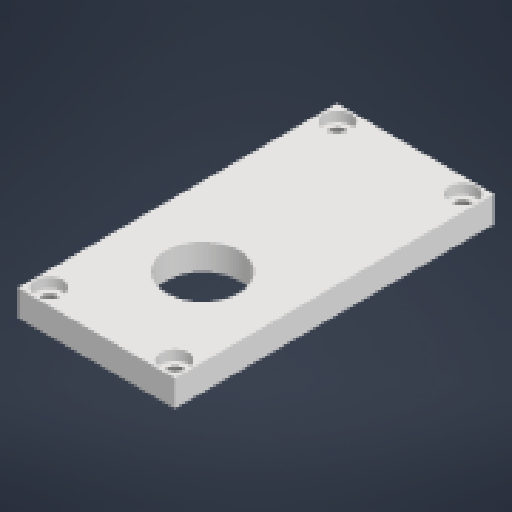
# Autodesk Inventor part: nắp
Saved by Autodesk Inventor 2026.2 (Build 302298000, 298)
## iProperties
Created: 2026-03-17
Part Number: nắp
Material: Generic
Document SubType Name: Modeling
Designer: thita
Density: 1 g/cm^3
Appearance: Default
Author: thita
Autodesk Inventor part; units mm, degrees
ref_plane "YZ Plane" through (0, 0, 0) normal (1, 0, 0) x (0, 1, 0)
ref_plane "XZ Plane" through (0, 0, 0) normal (0, 1, 0) x (-1, 0, 0)
sketch "Sketch1" plane through (0, 0, 0) normal (0, 1, 0) x (-1, 0, 0)
  line L0 (10.3, -25.8) -> (10.3, 25.8)
  line L1 (10.3, 25.8) -> (-10.3, 25.8)
  line L2 (-10.3, 25.8) -> (-10.3, -25.8)
  line L3 (-10.3, -25.8) -> (10.3, -25.8)
  line L4 (10.3, -25.8) -> (-10.3, 25.8) construction
  line L5 (10.3, 25.8) -> (-10.3, -25.8) construction
  line L6 (15, -30.5) -> (-14.9994, -30.5003)
  line L7 (-14.9994, -30.5003) -> (-15, 30.5)
  line L8 (-15, 30.5) -> (14.9994, 30.5003)
  line L9 (14.9994, 30.5003) -> (15, -30.5)
  line L10 (15, -30.5) -> (-15, 30.5) construction
  line L11 (-14.9994, -30.5003) -> (14.9994, 30.5003) construction
  line L12 (14.9994, 30.5003) -> (14.9995, 27.5003)
  line L13 (14.9995, 27.5003) -> (11.9995, 27.5002)
  circle A0 centre (11.9995, 27.5002) radius 1.5
  line L14 (14.9997, 0.0001) -> (12.9995, 0.0001)
  line L15 (0.0003, -30.5001) -> (0.0003, -27.8009)
  circle A1 centre (11.9995, -27.5) radius 1.5
  circle A2 centre (-11.9989, 27.5002) radius 1.5
  circle A3 centre (-11.9989, -27.5) radius 1.5
  point P0 (0, 0)
  point P1 (0, 0)
  dimension "d0" = 3
  dimension "d1" = 3
  dimension "d2" = 3
  constraints: 32 end point, 6 midpoint, 4 centre point, 4 parallel, 3 perpendicular, 3 symmetric about line, 1 coincident, 1 horizontal, 1 point on line, 1 vertical, 3 other
  measures "d0" distance of L8.end L12.end
  measures "d1" distance of L12.end L13.end
  measures "d2" diameter of A0
extrude "Extrusion1" add sketch "Sketch1" along normal blind 5 contours L3 L2 L1 L0 | L6 L7 L8 L9
sketch "Sketch2" plane through (0, 5, 0) normal (0, 1, 0) x (1, 0, 0)
  circle A0 centre (-11.9995, -27.5002) radius 1.5 projected
  circle A1 centre (-11.9995, -27.5002) radius 2.6
  circle A2 centre (11.9989, -27.5002) radius 1.5 projected
  circle A3 centre (11.9989, -27.5002) radius 2.6
  circle A4 centre (-11.9995, 27.5) radius 1.5 projected
  circle A5 centre (-11.9995, 27.5) radius 2.6
  circle A6 centre (11.9989, 27.5) radius 1.5 projected
  circle A7 centre (11.9989, 27.5) radius 2.6
  point P0 (0, 0)
  dimension "d5" = 5.2
  dimension "d6" = 5.2
  dimension "d7" = 5.2
  dimension "d8" = 5.2
  constraints: 4 centre point, 4 coincident
  measures "d5" diameter of A1
  measures "d6" diameter of A3
  measures "d7" diameter of A5
  measures "d8" diameter of A7
extrude "Extrusion2" cut sketch "Sketch2" against normal blind 2
thread "Thread1" size "M3x0.5" class "6H" standard "ISO Metric profile" length 12
thread "Thread2" size "M3x0.5" class "6H" standard "ISO Metric profile" length 12
thread "Thread3" size "M3x0.5" class "6H" standard "ISO Metric profile" length 12
thread "Thread4" size "M3x0.5" class "6H" standard "ISO Metric profile" length 12
ref_plane "Work Plane1" through (-23.1777, 0, -34.5208) normal (0, 1, 0) x (0, 0, 1)
sketch "Sketch3" plane through (0, 5, 0) normal (0, 1, 0) x (1, 0, 0)
  line L0 (1.9772, -9.9005) -> (1.8848, -9.962) projected
  arc A0 (1.9772, -9.9005) -> (1.973, -9.874) centre (-0.0002, -10.2001) ccw projected
  line L1 (1.8662, -9.8441) -> (1.973, -9.874) projected
  line L2 (1.9545, -9.777) -> (1.8662, -9.8441) projected
  arc A1 (1.9545, -9.777) -> (1.9487, -9.7507) centre (-0.0002, -10.2001) ccw projected
  line L3 (1.8401, -9.7276) -> (1.9487, -9.7507) projected
  line L4 (1.9241, -9.6551) -> (1.8401, -9.7276) projected
  arc A2 (1.9241, -9.6551) -> (1.9166, -9.6292) centre (-0.0002, -10.2001) ccw projected
  line L5 (1.8068, -9.613) -> (1.9166, -9.6292) projected
  line L6 (1.8861, -9.5353) -> (1.8068, -9.613) projected
  arc A3 (1.8861, -9.5353) -> (1.877, -9.51) centre (-0.0002, -10.2001) ccw projected
  line L7 (1.7664, -9.5007) -> (1.877, -9.51) projected
  line L8 (1.8406, -9.4182) -> (1.7664, -9.5007) projected
  arc A4 (1.8406, -9.4182) -> (1.8299, -9.3935) centre (-0.0002, -10.2001) ccw projected
  line L9 (1.719, -9.3911) -> (1.8299, -9.3935) projected
  line L10 (1.7879, -9.3041) -> (1.719, -9.3911) projected
  arc A5 (1.7879, -9.3041) -> (1.7757, -9.2802) centre (-0.0002, -10.2001) ccw projected
  line L11 (1.6648, -9.2848) -> (1.7757, -9.2802) projected
  line L12 (1.7281, -9.1936) -> (1.6648, -9.2848) projected
  arc A6 (1.7281, -9.1936) -> (1.7144, -9.1705) centre (-0.0002, -10.2001) ccw projected
  line L13 (1.604, -9.1821) -> (1.7144, -9.1705) projected
  line L14 (1.6615, -9.0871) -> (1.604, -9.1821) projected
  arc A7 (1.6615, -9.0871) -> (1.6464, -9.0649) centre (-0.0002, -10.2001) ccw projected
  line L15 (1.5369, -9.0833) -> (1.6464, -9.0649) projected
  line L16 (1.5883, -8.985) -> (1.5369, -9.0833) projected
  arc A8 (1.5883, -8.985) -> (1.5718, -8.9637) centre (-0.0002, -10.2001) ccw projected
  line L17 (1.4638, -8.989) -> (1.5718, -8.9637) projected
  line L18 (1.5089, -8.8876) -> (1.4638, -8.989) projected
  arc A9 (1.5089, -8.8876) -> (1.4911, -8.8674) centre (-0.0002, -10.2001) ccw projected
  line L19 (1.3848, -8.8995) -> (1.4911, -8.8674) projected
  line L20 (1.4235, -8.7954) -> (1.3848, -8.8995) projected
  arc A10 (1.4235, -8.7954) -> (1.4045, -8.7764) centre (-0.0002, -10.2001) ccw projected
  line L21 (1.3004, -8.8151) -> (1.4045, -8.7764) projected
  line L22 (1.3325, -8.7088) -> (1.3004, -8.8151) projected
  arc A11 (1.3325, -8.7088) -> (1.3123, -8.6911) centre (-0.0002, -10.2001) ccw projected
  line L23 (1.2109, -8.7362) -> (1.3123, -8.6911) projected
  line L24 (1.2362, -8.6281) -> (1.2109, -8.7362) projected
  arc A12 (1.2362, -8.6281) -> (1.215, -8.6116) centre (-0.0002, -10.2001) ccw projected
  line L25 (1.1166, -8.663) -> (1.215, -8.6116) projected
  line L26 (1.1351, -8.5536) -> (1.1166, -8.663) projected
  arc A13 (1.1351, -8.5536) -> (1.1128, -8.5384) centre (-0.0002, -10.2001) ccw projected
  line L27 (1.0179, -8.5959) -> (1.1128, -8.5384) projected
  line L28 (1.0294, -8.4855) -> (1.0179, -8.5959) projected
  arc A14 (1.0294, -8.4855) -> (1.0063, -8.4718) centre (-0.0002, -10.2001) ccw projected
  line L29 (0.9151, -8.5351) -> (1.0063, -8.4718) projected
  line L30 (0.9197, -8.4243) -> (0.9151, -8.5351) projected
  arc A15 (0.9197, -8.4243) -> (0.8958, -8.4121) centre (-0.0002, -10.2001) ccw projected
  line L31 (0.8088, -8.481) -> (0.8958, -8.4121) projected
  line L32 (0.8064, -8.37) -> (0.8088, -8.481) projected
  arc A16 (0.8064, -8.37) -> (0.7817, -8.3593) centre (-0.0002, -10.2001) ccw projected
  line L33 (0.6992, -8.4336) -> (0.7817, -8.3593) projected
  line L34 (0.6899, -8.323) -> (0.6992, -8.4336) projected
  arc A17 (0.6899, -8.323) -> (0.6646, -8.3139) centre (-0.0002, -10.2001) ccw projected
  line L35 (0.5869, -8.3931) -> (0.6646, -8.3139) projected
  line L36 (0.5707, -8.2833) -> (0.5869, -8.3931) projected
  arc A18 (0.5707, -8.2833) -> (0.5449, -8.2758) centre (-0.0002, -10.2001) ccw projected
  line L37 (0.4723, -8.3598) -> (0.5449, -8.2758) projected
  line L38 (0.4492, -8.2513) -> (0.4723, -8.3598) projected
  arc A19 (0.4492, -8.2513) -> (0.423, -8.2454) centre (-0.0002, -10.2001) ccw projected
  line L39 (0.3558, -8.3338) -> (0.423, -8.2454) projected
  line L40 (0.3259, -8.2269) -> (0.3558, -8.3338) projected
  arc A20 (0.3259, -8.2269) -> (0.2994, -8.2227) centre (-0.0002, -10.2001) ccw projected
  line L41 (0.2379, -8.3151) -> (0.2994, -8.2227) projected
  line L42 (0.2014, -8.2103) -> (0.2379, -8.3151) projected
  arc A21 (0.2014, -8.2103) -> (0.1746, -8.2078) centre (-0.0002, -10.2001) ccw projected
  line L43 (0.1191, -8.3039) -> (0.1746, -8.2078) projected
  line L44 (0.076, -8.2016) -> (0.1191, -8.3039) projected
  arc A22 (0.076, -8.2016) -> (0.0492, -8.2007) centre (-0.0002, -10.2001) ccw projected
  line L45 (-0.0002, -8.3001) -> (0.0492, -8.2007) projected
  line L46 (-0.0496, -8.2007) -> (-0.0002, -8.3001) projected
  arc A23 (-0.0496, -8.2007) -> (-0.0765, -8.2016) centre (-0.0002, -10.2001) ccw projected
  line L47 (-0.1195, -8.3039) -> (-0.0765, -8.2016) projected
  line L48 (-0.175, -8.2078) -> (-0.1195, -8.3039) projected
  arc A24 (-0.175, -8.2078) -> (-0.2018, -8.2103) centre (-0.0002, -10.2001) ccw projected
  line L49 (-0.2383, -8.3151) -> (-0.2018, -8.2103) projected
  line L50 (-0.2998, -8.2227) -> (-0.2383, -8.3151) projected
  arc A25 (-0.2998, -8.2227) -> (-0.3263, -8.2269) centre (-0.0002, -10.2001) ccw projected
  line L51 (-0.3562, -8.3338) -> (-0.3263, -8.2269) projected
  line L52 (-0.4234, -8.2454) -> (-0.3562, -8.3338) projected
  arc A26 (-0.4234, -8.2454) -> (-0.4496, -8.2513) centre (-0.0002, -10.2001) ccw projected
  line L53 (-0.4727, -8.3598) -> (-0.4496, -8.2513) projected
  line L54 (-0.5453, -8.2758) -> (-0.4727, -8.3598) projected
  arc A27 (-0.5453, -8.2758) -> (-0.5711, -8.2833) centre (-0.0002, -10.2001) ccw projected
  line L55 (-0.5873, -8.3931) -> (-0.5711, -8.2833) projected
  line L56 (-0.665, -8.3139) -> (-0.5873, -8.3931) projected
  arc A28 (-0.665, -8.3139) -> (-0.6903, -8.323) centre (-0.0002, -10.2001) ccw projected
  line L57 (-0.6996, -8.4336) -> (-0.6903, -8.323) projected
  line L58 (-0.7821, -8.3593) -> (-0.6996, -8.4336) projected
  arc A29 (-0.7821, -8.3593) -> (-0.8068, -8.37) centre (-0.0002, -10.2001) ccw projected
  line L59 (-0.8092, -8.481) -> (-0.8068, -8.37) projected
  line L60 (-0.8962, -8.4121) -> (-0.8092, -8.481) projected
  arc A30 (-0.8962, -8.4121) -> (-0.9201, -8.4243) centre (-0.0002, -10.2001) ccw projected
  line L61 (-0.9155, -8.5352) -> (-0.9201, -8.4243) projected
  line L62 (-1.0067, -8.4719) -> (-0.9155, -8.5352) projected
  arc A31 (-1.0067, -8.4719) -> (-1.0298, -8.4855) centre (-0.0002, -10.2001) ccw projected
  line L63 (-1.0183, -8.5959) -> (-1.0298, -8.4855) projected
  line L64 (-1.1132, -8.5385) -> (-1.0183, -8.5959) projected
  arc A32 (-1.1132, -8.5385) -> (-1.1355, -8.5536) centre (-0.0002, -10.2001) ccw projected
  line L65 (-1.117, -8.663) -> (-1.1355, -8.5536) projected
  line L66 (-1.2154, -8.6116) -> (-1.117, -8.663) projected
  arc A33 (-1.2154, -8.6116) -> (-1.2366, -8.6281) centre (-0.0002, -10.2001) ccw projected
  line L67 (-1.2113, -8.7362) -> (-1.2366, -8.6281) projected
  line L68 (-1.3127, -8.6911) -> (-1.2113, -8.7362) projected
  arc A34 (-1.3127, -8.6911) -> (-1.3329, -8.7088) centre (-0.0002, -10.2001) ccw projected
  line L69 (-1.3008, -8.8151) -> (-1.3329, -8.7088) projected
  line L70 (-1.4049, -8.7765) -> (-1.3008, -8.8151) projected
  arc A35 (-1.4049, -8.7765) -> (-1.4239, -8.7955) centre (-0.0002, -10.2001) ccw projected
  line L71 (-1.3852, -8.8995) -> (-1.4239, -8.7955) projected
  line L72 (-1.4915, -8.8675) -> (-1.3852, -8.8995) projected
  arc A36 (-1.4915, -8.8675) -> (-1.5093, -8.8876) centre (-0.0002, -10.2001) ccw projected
  line L73 (-1.4642, -8.989) -> (-1.5093, -8.8876) projected
  line L74 (-1.5722, -8.9637) -> (-1.4642, -8.989) projected
  arc A37 (-1.5722, -8.9637) -> (-1.5887, -8.985) centre (-0.0002, -10.2001) ccw projected
  line L75 (-1.5373, -9.0834) -> (-1.5887, -8.985) projected
  line L76 (-1.6468, -9.0649) -> (-1.5373, -9.0834) projected
  arc A38 (-1.6468, -9.0649) -> (-1.6619, -9.0871) centre (-0.0002, -10.2001) ccw projected
  line L77 (-1.6044, -9.1821) -> (-1.6619, -9.0871) projected
  line L78 (-1.7148, -9.1705) -> (-1.6044, -9.1821) projected
  arc A39 (-1.7148, -9.1705) -> (-1.7285, -9.1937) centre (-0.0002, -10.2001) ccw projected
  line L79 (-1.6652, -9.2848) -> (-1.7285, -9.1937) projected
  line L80 (-1.7761, -9.2802) -> (-1.6652, -9.2848) projected
  arc A40 (-1.7761, -9.2802) -> (-1.7883, -9.3042) centre (-0.0002, -10.2001) ccw projected
  line L81 (-1.7194, -9.3912) -> (-1.7883, -9.3042) projected
  line L82 (-1.8303, -9.3935) -> (-1.7194, -9.3912) projected
  arc A41 (-1.8303, -9.3935) -> (-1.841, -9.4182) centre (-0.0002, -10.2001) ccw projected
  line L83 (-1.7668, -9.5007) -> (-1.841, -9.4182) projected
  line L84 (-1.8774, -9.5101) -> (-1.7668, -9.5007) projected
  arc A42 (-1.8774, -9.5101) -> (-1.8865, -9.5353) centre (-0.0002, -10.2001) ccw projected
  line L85 (-1.8072, -9.613) -> (-1.8865, -9.5353) projected
  line L86 (-1.917, -9.6293) -> (-1.8072, -9.613) projected
  arc A43 (-1.917, -9.6293) -> (-1.9245, -9.6551) centre (-0.0002, -10.2001) ccw projected
  line L87 (-1.8405, -9.7276) -> (-1.9245, -9.6551) projected
  line L88 (-1.949, -9.7508) -> (-1.8405, -9.7276) projected
  arc A44 (-1.949, -9.7508) -> (-1.9549, -9.777) centre (-0.0002, -10.2001) ccw projected
  line L89 (-1.8665, -9.8441) -> (-1.9549, -9.777) projected
  line L90 (-1.9734, -9.874) -> (-1.8665, -9.8441) projected
  arc A45 (-1.9734, -9.874) -> (-1.9776, -9.9006) centre (-0.0002, -10.2001) ccw projected
  line L91 (-1.8852, -9.962) -> (-1.9776, -9.9006) projected
  line L92 (-1.99, -9.9986) -> (-1.8852, -9.962) projected
  arc A46 (-1.99, -9.9986) -> (-1.9925, -10.0253) centre (-0.0002, -10.2001) ccw projected
  line L93 (-1.8964, -10.0809) -> (-1.9925, -10.0253) projected
  line L94 (-1.9987, -10.1239) -> (-1.8964, -10.0809) projected
  arc A47 (-1.9987, -10.1239) -> (-1.9996, -10.1508) centre (-0.0002, -10.2001) ccw projected
  line L95 (-1.9002, -10.2002) -> (-1.9996, -10.1508) projected
  line L96 (-1.9996, -10.2495) -> (-1.9002, -10.2002) projected
  arc A48 (-1.9996, -10.2495) -> (-1.9987, -10.2764) centre (-0.0002, -10.2001) ccw projected
  line L97 (-1.8964, -10.3195) -> (-1.9987, -10.2764) projected
  line L98 (-1.9925, -10.375) -> (-1.8964, -10.3195) projected
  arc A49 (-1.9925, -10.375) -> (-1.99, -10.4017) centre (-0.0002, -10.2001) ccw projected
  line L99 (-1.8852, -10.4383) -> (-1.99, -10.4017) projected
  line L100 (-1.9776, -10.4997) -> (-1.8852, -10.4383) projected
  arc A50 (-1.9776, -10.4997) -> (-1.9734, -10.5263) centre (-0.0002, -10.2001) ccw projected
  line L101 (-1.8665, -10.5562) -> (-1.9734, -10.5263) projected
  line L102 (-1.9549, -10.6233) -> (-1.8665, -10.5562) projected
  arc A51 (-1.9549, -10.6233) -> (-1.949, -10.6495) centre (-0.0002, -10.2001) ccw projected
  line L103 (-1.8405, -10.6727) -> (-1.949, -10.6495) projected
  line L104 (-1.9245, -10.7452) -> (-1.8405, -10.6727) projected
  arc A52 (-1.9245, -10.7452) -> (-1.917, -10.771) centre (-0.0002, -10.2001) ccw projected
  line L105 (-1.8072, -10.7873) -> (-1.917, -10.771) projected
  line L106 (-1.8864, -10.865) -> (-1.8072, -10.7873) projected
  arc A53 (-1.8864, -10.865) -> (-1.8773, -10.8903) centre (-0.0002, -10.2001) ccw projected
  line L107 (-1.7668, -10.8996) -> (-1.8773, -10.8903) projected
  line L108 (-1.841, -10.9821) -> (-1.7668, -10.8996) projected
  arc A54 (-1.841, -10.9821) -> (-1.8303, -11.0068) centre (-0.0002, -10.2001) ccw projected
  line L109 (-1.7193, -11.0091) -> (-1.8303, -11.0068) projected
  line L110 (-1.7882, -11.0961) -> (-1.7193, -11.0091) projected
  arc A55 (-1.7882, -11.0961) -> (-1.776, -11.1201) centre (-0.0002, -10.2001) ccw projected
  line L111 (-1.6652, -11.1155) -> (-1.776, -11.1201) projected
  line L112 (-1.7285, -11.2066) -> (-1.6652, -11.1155) projected
  arc A56 (-1.7285, -11.2066) -> (-1.7148, -11.2298) centre (-0.0002, -10.2001) ccw projected
  line L113 (-1.6044, -11.2182) -> (-1.7148, -11.2298) projected
  line L114 (-1.6619, -11.3132) -> (-1.6044, -11.2182) projected
  arc A57 (-1.6619, -11.3132) -> (-1.6467, -11.3354) centre (-0.0002, -10.2001) ccw projected
  line L115 (-1.5373, -11.3169) -> (-1.6467, -11.3354) projected
  line L116 (-1.5887, -11.4153) -> (-1.5373, -11.3169) projected
  arc A58 (-1.5887, -11.4153) -> (-1.5722, -11.4366) centre (-0.0002, -10.2001) ccw projected
  line L117 (-1.4641, -11.4113) -> (-1.5722, -11.4366) projected
  line L118 (-1.5092, -11.5127) -> (-1.4641, -11.4113) projected
  arc A59 (-1.5092, -11.5127) -> (-1.4915, -11.5328) centre (-0.0002, -10.2001) ccw projected
  line L119 (-1.3852, -11.5008) -> (-1.4915, -11.5328) projected
  line L120 (-1.4239, -11.6048) -> (-1.3852, -11.5008) projected
  arc A60 (-1.4239, -11.6048) -> (-1.4049, -11.6238) centre (-0.0002, -10.2001) ccw projected
  line L121 (-1.3008, -11.5852) -> (-1.4049, -11.6238) projected
  line L122 (-1.3328, -11.6915) -> (-1.3008, -11.5852) projected
  arc A61 (-1.3328, -11.6915) -> (-1.3127, -11.7092) centre (-0.0002, -10.2001) ccw projected
  line L123 (-1.2113, -11.6641) -> (-1.3127, -11.7092) projected
  line L124 (-1.2366, -11.7722) -> (-1.2113, -11.6641) projected
  arc A62 (-1.2366, -11.7722) -> (-1.2153, -11.7887) centre (-0.0002, -10.2001) ccw projected
  line L125 (-1.117, -11.7373) -> (-1.2153, -11.7887) projected
  line L126 (-1.1354, -11.8467) -> (-1.117, -11.7373) projected
  arc A63 (-1.1354, -11.8467) -> (-1.1132, -11.8618) centre (-0.0002, -10.2001) ccw projected
  line L127 (-1.0182, -11.8044) -> (-1.1132, -11.8618) projected
  line L128 (-1.0298, -11.9148) -> (-1.0182, -11.8044) projected
  arc A64 (-1.0298, -11.9148) -> (-1.0067, -11.9284) centre (-0.0002, -10.2001) ccw projected
  line L129 (-0.9155, -11.8651) -> (-1.0067, -11.9284) projected
  line L130 (-0.9201, -11.976) -> (-0.9155, -11.8651) projected
  arc A65 (-0.9201, -11.976) -> (-0.8962, -11.9882) centre (-0.0002, -10.2001) ccw projected
  line L131 (-0.8091, -11.9193) -> (-0.8962, -11.9882) projected
  line L132 (-0.8068, -12.0303) -> (-0.8091, -11.9193) projected
  arc A66 (-0.8068, -12.0303) -> (-0.7821, -12.0409) centre (-0.0002, -10.2001) ccw projected
  line L133 (-0.6996, -11.9667) -> (-0.7821, -12.0409) projected
  line L134 (-0.6903, -12.0773) -> (-0.6996, -11.9667) projected
  arc A67 (-0.6903, -12.0773) -> (-0.665, -12.0864) centre (-0.0002, -10.2001) ccw projected
  line L135 (-0.5873, -12.0071) -> (-0.665, -12.0864) projected
  line L136 (-0.571, -12.1169) -> (-0.5873, -12.0071) projected
  arc A68 (-0.571, -12.1169) -> (-0.5452, -12.1244) centre (-0.0002, -10.2001) ccw projected
  line L137 (-0.4727, -12.0404) -> (-0.5452, -12.1244) projected
  line L138 (-0.4496, -12.149) -> (-0.4727, -12.0404) projected
  arc A69 (-0.4496, -12.149) -> (-0.4233, -12.1549) centre (-0.0002, -10.2001) ccw projected
  line L139 (-0.3562, -12.0665) -> (-0.4233, -12.1549) projected
  line L140 (-0.3263, -12.1734) -> (-0.3562, -12.0665) projected
  arc A70 (-0.3263, -12.1734) -> (-0.2998, -12.1776) centre (-0.0002, -10.2001) ccw projected
  line L141 (-0.2383, -12.0852) -> (-0.2998, -12.1776) projected
  line L142 (-0.2018, -12.19) -> (-0.2383, -12.0852) projected
  arc A71 (-0.2018, -12.19) -> (-0.175, -12.1925) centre (-0.0002, -10.2001) ccw projected
  line L143 (-0.1195, -12.0964) -> (-0.175, -12.1925) projected
  line L144 (-0.0764, -12.1987) -> (-0.1195, -12.0964) projected
  arc A72 (-0.0764, -12.1987) -> (-0.0496, -12.1995) centre (-0.0002, -10.2001) ccw projected
  line L145 (-0.0002, -12.1001) -> (-0.0496, -12.1995) projected
  line L146 (0.0492, -12.1995) -> (-0.0002, -12.1001) projected
  arc A73 (0.0492, -12.1995) -> (0.0761, -12.1987) centre (-0.0002, -10.2001) ccw projected
  line L147 (0.1191, -12.0964) -> (0.0761, -12.1987) projected
  line L148 (0.1747, -12.1925) -> (0.1191, -12.0964) projected
  arc A74 (0.1747, -12.1925) -> (0.2014, -12.1899) centre (-0.0002, -10.2001) ccw projected
  line L149 (0.238, -12.0852) -> (0.2014, -12.1899) projected
  line L150 (0.2994, -12.1776) -> (0.238, -12.0852) projected
  arc A75 (0.2994, -12.1776) -> (0.326, -12.1734) centre (-0.0002, -10.2001) ccw projected
  line L151 (0.3559, -12.0665) -> (0.326, -12.1734) projected
  line L152 (0.423, -12.1549) -> (0.3559, -12.0665) projected
  arc A76 (0.423, -12.1549) -> (0.4492, -12.149) centre (-0.0002, -10.2001) ccw projected
  line L153 (0.4723, -12.0404) -> (0.4492, -12.149) projected
  line L154 (0.5449, -12.1244) -> (0.4723, -12.0404) projected
  arc A77 (0.5449, -12.1244) -> (0.5707, -12.1169) centre (-0.0002, -10.2001) ccw projected
  line L155 (0.587, -12.0071) -> (0.5707, -12.1169) projected
  line L156 (0.6647, -12.0864) -> (0.587, -12.0071) projected
  arc A78 (0.6647, -12.0864) -> (0.6899, -12.0773) centre (-0.0002, -10.2001) ccw projected
  line L157 (0.6993, -11.9667) -> (0.6899, -12.0773) projected
  line L158 (0.7818, -12.0409) -> (0.6993, -11.9667) projected
  arc A79 (0.7818, -12.0409) -> (0.8064, -12.0303) centre (-0.0002, -10.2001) ccw projected
  line L159 (0.8088, -11.9193) -> (0.8064, -12.0303) projected
  line L160 (0.8958, -11.9882) -> (0.8088, -11.9193) projected
  arc A80 (0.8958, -11.9882) -> (0.9198, -11.976) centre (-0.0002, -10.2001) ccw projected
  line L161 (0.9152, -11.8651) -> (0.9198, -11.976) projected
  line L162 (1.0063, -11.9284) -> (0.9152, -11.8651) projected
  arc A81 (1.0063, -11.9284) -> (1.0295, -11.9147) centre (-0.0002, -10.2001) ccw projected
  line L163 (1.0179, -11.8044) -> (1.0295, -11.9147) projected
  line L164 (1.1129, -11.8618) -> (1.0179, -11.8044) projected
  arc A82 (1.1129, -11.8618) -> (1.1351, -11.8467) centre (-0.0002, -10.2001) ccw projected
  line L165 (1.1166, -11.7373) -> (1.1351, -11.8467) projected
  line L166 (1.215, -11.7886) -> (1.1166, -11.7373) projected
  arc A83 (1.215, -11.7886) -> (1.2362, -11.7722) centre (-0.0002, -10.2001) ccw projected
  line L167 (1.2109, -11.6641) -> (1.2362, -11.7722) projected
  line L168 (1.3123, -11.7092) -> (1.2109, -11.6641) projected
  arc A84 (1.3123, -11.7092) -> (1.3325, -11.6914) centre (-0.0002, -10.2001) ccw projected
  line L169 (1.3005, -11.5852) -> (1.3325, -11.6914) projected
  line L170 (1.4045, -11.6238) -> (1.3005, -11.5852) projected
  arc A85 (1.4045, -11.6238) -> (1.4235, -11.6048) centre (-0.0002, -10.2001) ccw projected
  line L171 (1.3849, -11.5008) -> (1.4235, -11.6048) projected
  line L172 (1.4911, -11.5328) -> (1.3849, -11.5008) projected
  arc A86 (1.4911, -11.5328) -> (1.5089, -11.5126) centre (-0.0002, -10.2001) ccw projected
  line L173 (1.4638, -11.4112) -> (1.5089, -11.5126) projected
  line L174 (1.5719, -11.4365) -> (1.4638, -11.4112) projected
  arc A87 (1.5719, -11.4365) -> (1.5883, -11.4153) centre (-0.0002, -10.2001) ccw projected
  line L175 (1.537, -11.3169) -> (1.5883, -11.4153) projected
  line L176 (1.6464, -11.3354) -> (1.537, -11.3169) projected
  arc A88 (1.6464, -11.3354) -> (1.6615, -11.3131) centre (-0.0002, -10.2001) ccw projected
  line L177 (1.604, -11.2182) -> (1.6615, -11.3131) projected
  line L178 (1.7144, -11.2297) -> (1.604, -11.2182) projected
  arc A89 (1.7144, -11.2297) -> (1.7281, -11.2066) centre (-0.0002, -10.2001) ccw projected
  line L179 (1.6648, -11.1155) -> (1.7281, -11.2066) projected
  line L180 (1.7757, -11.1201) -> (1.6648, -11.1155) projected
  arc A90 (1.7757, -11.1201) -> (1.7879, -11.0961) centre (-0.0002, -10.2001) ccw projected
  line L181 (1.719, -11.0091) -> (1.7879, -11.0961) projected
  line L182 (1.83, -11.0067) -> (1.719, -11.0091) projected
  arc A91 (1.83, -11.0067) -> (1.8406, -10.9821) centre (-0.0002, -10.2001) ccw projected
  line L183 (1.7664, -10.8996) -> (1.8406, -10.9821) projected
  line L184 (1.877, -10.8902) -> (1.7664, -10.8996) projected
  arc A92 (1.877, -10.8902) -> (1.8861, -10.8649) centre (-0.0002, -10.2001) ccw projected
  line L185 (1.8068, -10.7873) -> (1.8861, -10.8649) projected
  line L186 (1.9166, -10.771) -> (1.8068, -10.7873) projected
  arc A93 (1.9166, -10.771) -> (1.9241, -10.7452) centre (-0.0002, -10.2001) ccw projected
  line L187 (1.8401, -10.6726) -> (1.9241, -10.7452) projected
  line L188 (1.9487, -10.6495) -> (1.8401, -10.6726) projected
  arc A94 (1.9487, -10.6495) -> (1.9545, -10.6233) centre (-0.0002, -10.2001) ccw projected
  line L189 (1.8662, -10.5561) -> (1.9545, -10.6233) projected
  line L190 (1.973, -10.5263) -> (1.8662, -10.5561) projected
  arc A95 (1.973, -10.5263) -> (1.9773, -10.4997) centre (-0.0002, -10.2001) ccw projected
  line L191 (1.8848, -10.4383) -> (1.9773, -10.4997) projected
  line L192 (1.9896, -10.4017) -> (1.8848, -10.4383) projected
  arc A96 (1.9896, -10.4017) -> (1.9922, -10.375) centre (-0.0002, -10.2001) ccw projected
  line L193 (1.8961, -10.3194) -> (1.9922, -10.375) projected
  line L194 (1.9984, -10.2764) -> (1.8961, -10.3194) projected
  arc A97 (1.9984, -10.2764) -> (1.9992, -10.2495) centre (-0.0002, -10.2001) ccw projected
  line L195 (1.8998, -10.2001) -> (1.9992, -10.2495) projected
  line L196 (1.9992, -10.1507) -> (1.8998, -10.2001) projected
  arc A98 (1.9992, -10.1507) -> (1.9984, -10.1239) centre (-0.0002, -10.2001) ccw projected
  line L197 (1.8961, -10.0808) -> (1.9984, -10.1239) projected
  line L198 (1.9922, -10.0253) -> (1.8961, -10.0808) projected
  arc A99 (1.9922, -10.0253) -> (1.9896, -9.9985) centre (-0.0002, -10.2001) ccw projected
  line L199 (1.8848, -9.962) -> (1.9896, -9.9985) projected
  circle A100 centre (-0.0002, -10.2001) radius 7
  point P0 (0, 0)
  dimension "d19" = 14
  constraints: 1 centre point, 1 coincident
  measures "d19" diameter of A100
extrude "Extrusion3" cut sketch "Sketch3" against normal up to surface (5 mm away) contours L0 L199 A99 L198 L197 A98 L196 L195 A97 L194 L193 A96 L192 L191 A95 L190 L189 A94 L188 L187 A93 L186 L185 A92 L184 L183 A91 L182 L181 A90 L180 L179 A89 L178 L177 A88 L176 L175 A87 L174 L173 A86 L172 L171 A85 L170 L169 A84 L168 L167 A83 L166 L165 A82 L164 L163 A81 L162 L161 A80 L160 L159 A79 L158 L157 A78 L156 L155 A77 L154 L153 A76 L152 L151 A75 L150 L149 A74 L148 L147 A73 L146 L145 A72 L144 L143 A71 L142 L141 A70 L140 L139 A69 L138 L137 A68 L136 L135 A67 L134 L133 A66 L132 L131 A65 L130 L129 A64 L128 L127 A63 L126 L125 A62 L124 L123 A61 L122 L121 A60 L120 L119 A59 L118 L117 A58 L116 L115 A57 L114 L113 A56 L112 L111 A55 L110 L109 A54 L108 L107 A53 L106 L105 A52 L104 L103 A51 L102 L101 A50 L100 L99 A49 L98 L97 A48 L96 L95 A47 L94 L93 A46 L92 L91 A45 L90 L89 A44 L88 L87 A43 L86 L85 A42 L84 L83 A41 L82 L81 A40 L80 L79 A39 L78 L77 A38 L76 L75 A37 L74 L73 A36 L72 L71 A35 L70 L69 A34 L68 L67 A33 L66 L65 A32 L64 L63 A31 L62 L61 A30 L60 L59 A29 L58 L57 A28 L56 L55 A27 L54 L53 A26 L52 L51 A25 L50 L49 A24 L48 L47 A23 L46 L45 A22 L44 L43 A21 L42 L41 A20 L40 L39 A19 L38 L37 A18 L36 L35 A17 L34 L33 A16 L32 L31 A15 L30 L29 A14 L28 L27 A13 L26 L25 A12 L24 L23 A11 L22 L21 A10 L20 L19 A9 L18 L17 A8 L16 L15 A7 L14 L13 A6 L12 L11 A5 L10 L9 A4 L8 L7 A3 L6 L5 A2 L4 L3 A1 L2 L1 A0 | A100
body "Solid1"
